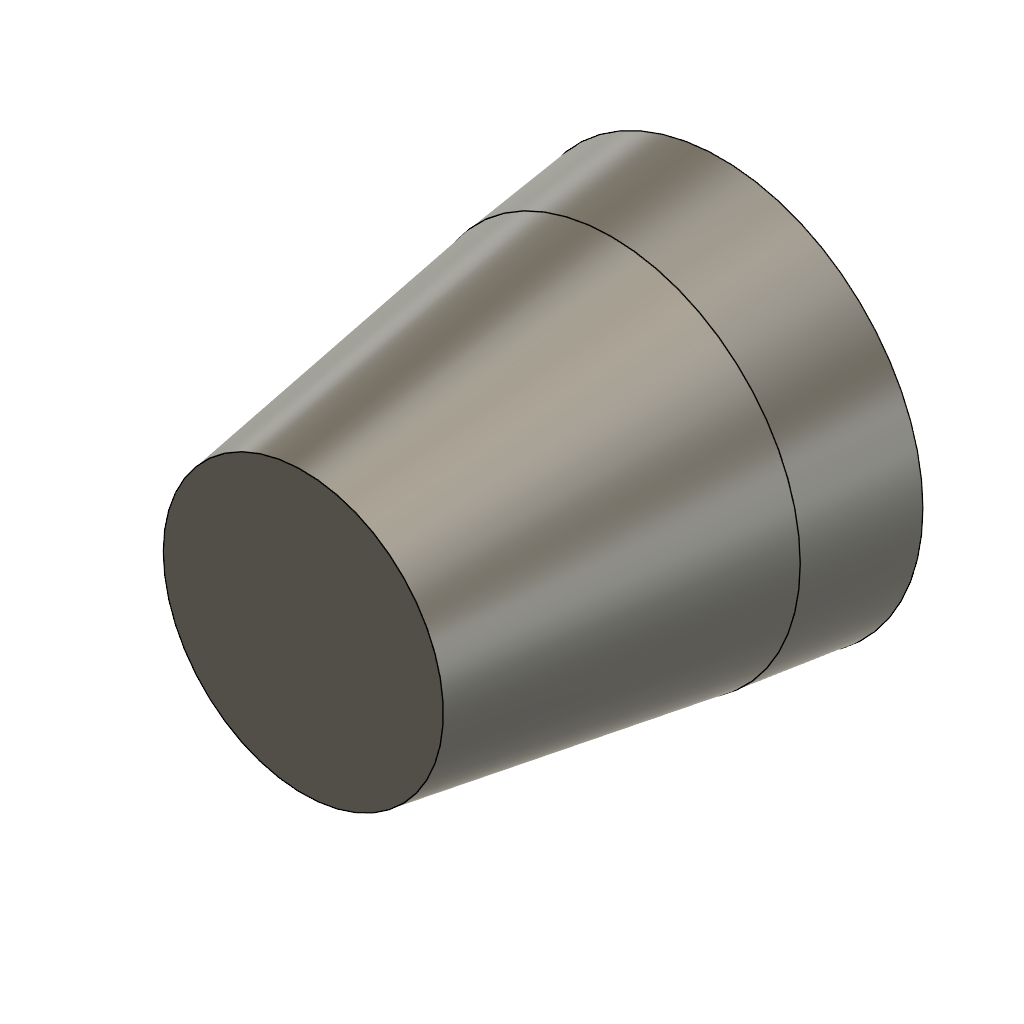
holdout_b_edit_draft_second (Autodesk Fusion 360 design; units mm, degrees)
part number: 2026-11-27-16-39-54-575
Autodesk Fusion 360 part; units mm, degrees
sketch "CircularProfile" plane through (0, 0, 0) normal (0, 0, 1) x (1, 0, 0)
  circle A0 centre (-9, -17) radius 19
extrude "TwoSidedDraft" add sketch "CircularProfile" along normal blind 31 draft -9 and the other way blind 11 draft 7
